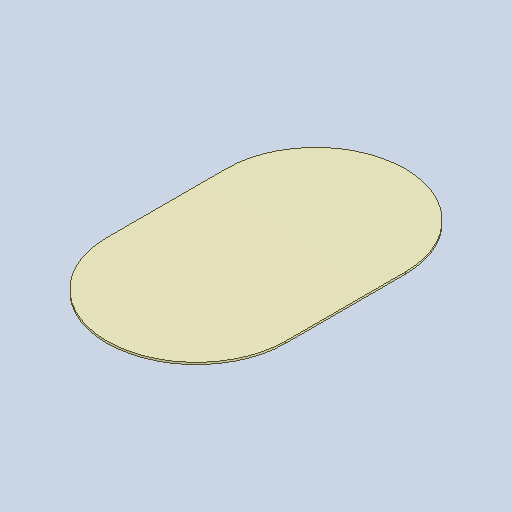
# Autodesk Inventor part: RDS-1101 Tank Bottom PP
Saved by Autodesk Inventor 2026.2 (Build 302298000, 298)
## iProperties
Created: 2026-10-18
Part Number: RDS-1101 Tank Bottom PP
Material: Polypropylene
Description: Tank bottom plate, polypropylene
Document SubType Name: Modeling
Designer: admin
Stock Number: Дно ёмкости ПП
Density: 0.899 g/cm^3
Appearance: Smooth - Ash
Author: admin
Autodesk Inventor part; units mm, degrees
ref_plane "YZ Plane" through (0, 0, 0) normal (1, 0, 0) x (0, 1, 0)
ref_plane "XZ Plane" through (0, 0, 0) normal (0, 1, 0) x (-1, 0, 0)
ref_plane "XY Plane" through (0, 0, 0) normal (0, 0, 1) x (1, 0, 0)
sketch "Sketch1" plane through (0, 0, 0) normal (0, 1, 0) x (-1, 0, 0)
  line L0 (-450, -300) -> (-450, 300)
  line L1 (450, 300) -> (450, -300)
  arc A0 (450, 300) -> (-450, 300) centre (0, 300) ccw
  arc A1 (-450, -300) -> (450, -300) centre (0, -300) ccw
  dimension "d0" = 450
  dimension "d1" = 600
  constraints: 4 end point, 4 point on circle, 4 tangent, 2 centre point, 1 equal radius
  measures "d0" radius of A0
  measures "d1" distance of L0.start L0.end
extrude "Plate" add sketch "Sketch1" along normal blind 10
equation "\"d0\" = 0.5 * Bottom1101_Width"
equation "\"d1\" = Bottom1101_Length - Bottom1101_Width"
equation "\"d2\" = Bottom1101_Thickness"
equation "\"Bottom1101_Length\" = 1500"
equation "\"Bottom1101_Width\" = 900"
equation "\"Bottom1101_Thickness\" = 10"
body "Solid1"
